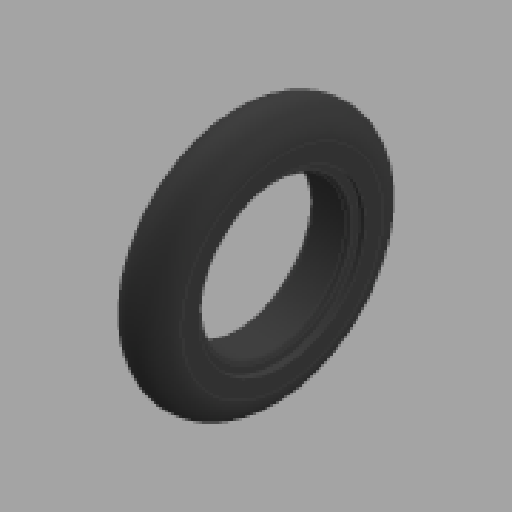
# Autodesk Inventor part: Tire
Saved by Autodesk Inventor 2025 (Build 290162000, 162)
## iProperties
Created: 2024-11-06
Part Number: Tire
Material: 일반
Document SubType Name: Modeling
Designer: OSB
Density: 0.485044 g/cm^3
Appearance: 기본값
Mass: 159.35 g
Surface Area: 413.025 cm^2
Volume: 328.527 cm^3
Author: OSB
Autodesk Inventor part; units mm, degrees
ref_plane "YZ Plane" through (0, 0, 0) normal (1, 0, 0) x (0, 1, 0)
ref_plane "XZ Plane" through (0, 0, 0) normal (0, 1, 0) x (-1, 0, 0)
ref_plane "XY Plane" through (0, 0, 0) normal (0, 0, 1) x (1, 0, 0)
sketch "스케치3" plane through (0, 0, 0) normal (0, 0, 1) x (1, 0, 0)
  line L0 (41.5, -11.5) -> (41.5, 11.5)
  line L1 (41.5, 11.5) -> (47.5, 11.5)
  line L2 (47.5, 11.5) -> (47.5, 15)
  line L3 (41.5, -11.5) -> (47.5, -11.5)
  line L4 (47.5, -11.5) -> (47.5, -15)
  line L5 (0, 0) -> (41.5, 0) construction
  line L6 (47.5, -15) -> (57.5, -15)
  line L7 (47.5, 15) -> (57.5, 15)
  arc A0 (57.5, -15) -> (57.5, 15) centre (57.5, 0) ccw
  line L8 (72.5, -29.5897) -> (72.5, 31.6097) construction
  line L9 (0, -41.8296) -> (0, 43.8496) projected
  point P0 (72.5, 0)
  dimension "d9" = 41.5
  dimension "d10" = 23
  constraints: 18 end point, 4 horizontal, 3 perpendicular, 3 point on circle, 3 tangent, 2 horizontal alignment, 2 vertical, 1 centre point, 1 midpoint, 1 parallel, 1 vertical alignment, 1 other
  measures "d9" distance of L5.start L5.end
  measures "d10" distance of L0.start L0.end
revolve "회전1" add sketch "스케치3" angle 360 about axis through (0, -10, 0) along (0, 1, 0)
fillet "모깎기2" radius 2 2 edges at (-41.5, -11.5, 0) (-41.5, 11.5, 0)
